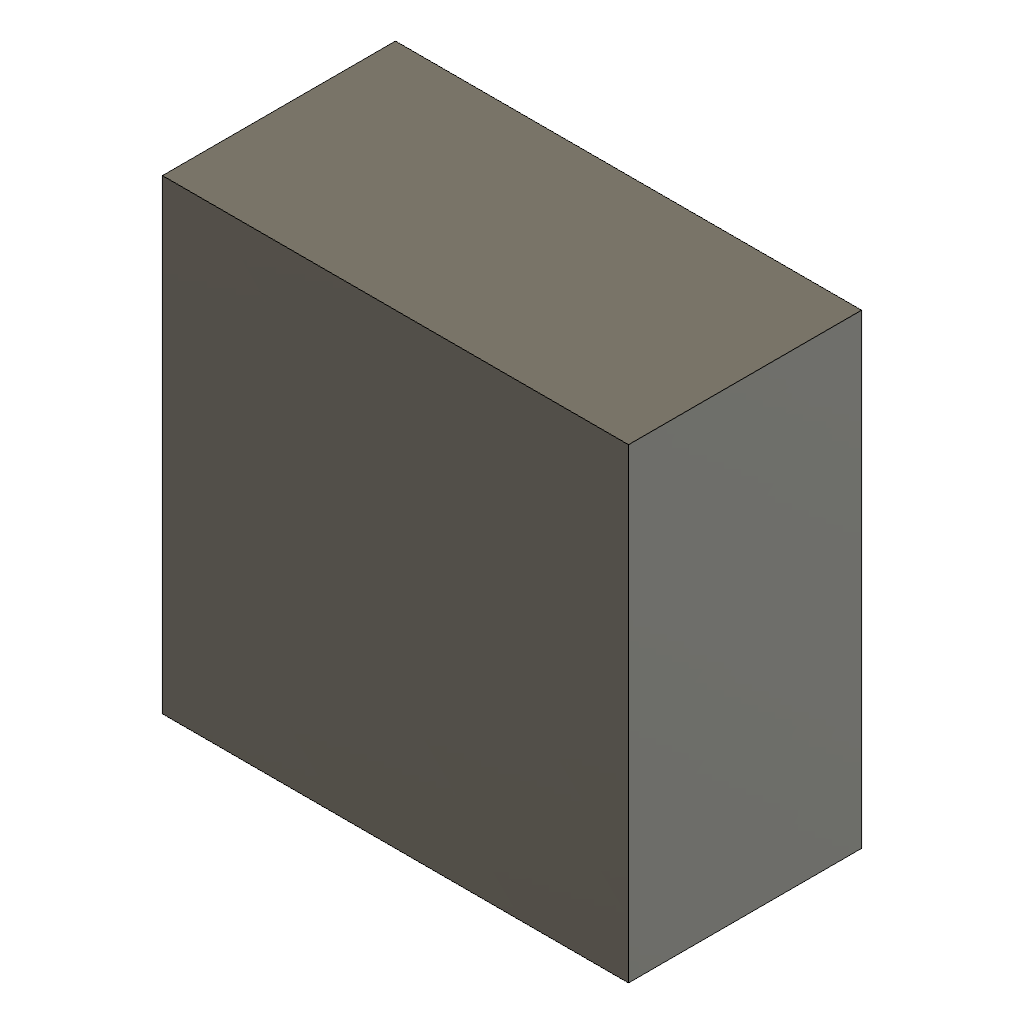
reverse_rectangle_creation (Autodesk Fusion 360 design; units mm, degrees)
part number: 2026-10-21-12-03-44-817
Autodesk Fusion 360 part; units mm, degrees
sketch "TrimmedProfileSources" plane through (0, 0, 0) normal (0, 0, 1) x (1, 0, 0)
  line L0 (20, -10) -> (50, -10)
  line L1 (50, -10) -> (50, 20)
  line L2 (50, 20) -> (20, 20)
  line L3 (20, 20) -> (20, -10)
  line L4 (0, 0) -> (40, 0)
  line L5 (40, 0) -> (40, 30)
  line L6 (40, 30) -> (0, 30)
  line L7 (0, 30) -> (0, 0)
extrude "SelectedTrimmedProfile" add sketch "TrimmedProfileSources" along normal blind 10 contours L2 L3 L4 L5
